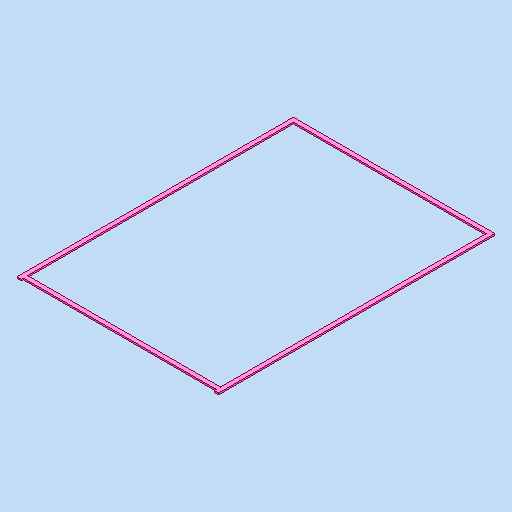
# Autodesk Inventor part: MM0861AN105_G11_301
Saved by Autodesk Inventor 2023.3 (Build 273359000, 359)
## iProperties
Part Number: MM0861AN105_G11_301
Material: Generisch
Description: =<RBPARTNOTITLE2>
Document SubType Name: Modeling
Designer: ric7an
Mass: 106.348 g
Surface Area: 725.1 cm^2
Volume: 106.348 cm^3
Density: 1 g/cm^3
Appearance: pink AnP
Vendor: Haewa
RBDOCUMENTTYPE: DRF
RBDOCUMENTVERSION: 00
RBDRAWINGMAINSCALE: 1:1
RBDRAWINGMISSINGSPEC: --
RBDRAWINGVOLUME: --
RBGBEDGESIN1: +0,5
RBGBEDGESIN2: +0,2
RBGBEDGESOUT1: -0,3
RBGBEDGESOUT2: -0,1
RBMATERIAL: --
RBMATMEETS: --
RBMATNO: =<Part Number>
RBPARTMADEOF: 3080-0102-18-00 / 2,5 m
RBPARTNO: SIEHE MNR
RBPARTNOTITLE1: gasket
RBPARTNOTITLE2: Dichtungsgummi sebstklebend
RBPARTSAFETYINDICATOR: --
RBSURFACE: --
RBSURFACE2: --
RBZEDGESNORM: ISO13715:2002-06
RBZGENDIMCLASS: m
RBZGENDIMNORM: ISO 2768-1:1989-11
RBZGENGEOCLASS: H
RBZGENGEONORM: ISO 2768-2:1989-11
RBZSURFACENORM: ISO13D2:2002-02
RBZTOLERANCENORM: ISO 14405-1:2010-12
AnP_Material: =<Material>
AnP_TemplVers: 20190222
AnP_Kategorie: 2
Author: ric7an
Keywords: =<RBPARTMADEOF>
Comments: =<RBSURFACE2>
Revision Number: 01
Autodesk Inventor part; units mm, degrees
ref_plane "YZ Plane" through (0, 0, 0) normal (1, 0, 0) x (0, 1, 0)
ref_plane "XZ Plane" through (0, 0, 0) normal (0, 1, 0) x (-1, 0, 0)
ref_plane "XY Plane" through (0, 0, 0) normal (0, 0, 1) x (1, 0, 0)
sketch "Skizze1" plane through (0, 0, 0) normal (0, 0, 1) x (1, 0, 0)
  line L0 (-259.5, 0) -> (259.5, 0)
  line L1 (259.5, 0) -> (259.5, 711.5)
  line L2 (259.5, 711.5) -> (-259.5, 711.5)
  line L3 (-259.5, 711.5) -> (-259.5, 0)
  line L4 (248.5, 700.5) -> (-248.5, 700.5)
  line L5 (-248.5, 700.5) -> (-248.5, 0)
  line L6 (-248.5, 0) -> (248.5, 0)
  line L7 (248.5, 0) -> (248.5, 700.5)
  line L8 (0, 853.8) -> (0, -142.3) projected
  line L9 (-363.3, 0) -> (363.3, 0) projected
  point P0 (0, 0)
  dimension "d0" = 11
  dimension "d1" = 11
  dimension "d2" = 711.5
  dimension "d7" = 497
  constraints: 16 end point, 4 parallel, 2 horizontal, 2 perpendicular, 1 collinear, 1 point on line, 2 other
  measures "d0" distance between parallel lines of L5 L3
  measures "d1" distance between parallel lines of L2 L4
  measures "d2" distance of L0.end L1.end
  measures "d7" distance between parallel lines of L7 L5
extrude "Extrusion1" add sketch "Skizze1" along normal blind 4 contours L3 L2 L8 L4 L5 L0 | L2 L1 L0 L7 L4 L8
sketch "Skizze3" plane through (259.5, 0, 0) normal (1, 0, 0) x (0, 0, -1)
  line L0 (0, 0) -> (0, 711.5) projected
  line L1 (0, 711.5) -> (-4, 711.5) projected
  line L2 (-4, 0) -> (-4, 711.5) projected
  line L3 (0, 0) -> (-4, 0) projected
  line L4 (0, 5) -> (-4, 5)
  line L5 (-4, 5) -> (-4, 16)
  line L6 (-4, 16) -> (0, 16)
  line L7 (0, 16) -> (0, 5)
  point P0 (0, 0)
  dimension "d11" = 11
  dimension "d12" = 5
  constraints: 8 end point, 2 parallel, 2 point on line, 1 horizontal, 1 perpendicular
  measures "d11" distance between parallel lines of L4 L6
  measures "d12" distance between parallel lines of L4 L3
extrude "Extrusion3" add sketch "Skizze3" against normal up to next contours L4 L2 L6 L0
equation "\"d1\" = d0"
